Autodesk Fusion 360 part; units mm, degrees
(part 2 of 4)
ref_plane "工作平面9" through (0, -260, 0) normal (0, 1, 0) x (0, 0, 1) in component "07_GPU_REINFORCED_REAR_TOWER"
sketch "草图9 (5)" plane through (0, -260, 0) normal (0, 1, 0) x (1, 0, 0) in component "07_GPU_REINFORCED_REAR_TOWER"
  circle A0 through (81.7, -151, 520) (79.15, -149.5278, 520) (79.15, -152.4722, 520)
extrude "Lower tab receiver height adjustment lower end" cut sketch "草图9 (5)" along normal blind 10 contours A0 in plane through (0, 260, 0) normal (0, 1, 0) bodies 26 in component "07_GPU_REINFORCED_REAR_TOWER"
ref_plane "工作平面10" through (0, -260, 0) normal (0, 1, 0) x (0, 0, 1) in component "07_GPU_REINFORCED_REAR_TOWER"
sketch "草图10 (3)" plane through (0, -260, 0) normal (0, 1, 0) x (1, 0, 0) in component "07_GPU_REINFORCED_REAR_TOWER"
  circle A0 through (81.7, -165, 520) (79.15, -163.5278, 520) (79.15, -166.4722, 520)
extrude "Lower tab receiver height adjustment upper end" cut sketch "草图10 (3)" along normal blind 10 contours A0 in plane through (0, 260, 0) normal (0, 1, 0) bodies 26 in component "07_GPU_REINFORCED_REAR_TOWER"
ref_plane "工作平面11" through (0, -260, 0) normal (0, 1, 0) x (0, 0, 1) in component "07_GPU_REINFORCED_REAR_TOWER"
sketch "草图11 (2)" plane through (0, -260, 0) normal (0, 1, 0) x (1, 0, 0) in component "07_GPU_REINFORCED_REAR_TOWER"
  line L0 (78.3, -151, 520) -> (81.7, -151, 520)
  line L1 (81.7, -151, 520) -> (81.7, -165, 520)
  line L2 (81.7, -165, 520) -> (78.3, -165, 520)
  line L3 (78.3, -165, 520) -> (78.3, -151, 520)
extrude "Lower tab receiver height adjustment web" cut sketch "草图11 (2)" along normal blind 10 contours L0 L1 L2 L3 in plane through (0, 260, 0) normal (0, 1, 0) bodies 26 in component "07_GPU_REINFORCED_REAR_TOWER"
ref_plane "工作平面12" through (0, -260, 0) normal (0, 1, 0) x (0, 0, 1) in component "07_GPU_REINFORCED_REAR_TOWER"
sketch "草图12 (2)" plane through (0, -260, 0) normal (0, 1, 0) x (1, 0, 0) in component "07_GPU_REINFORCED_REAR_TOWER"
  circle A0 through (165.7, -262, 520) (163.15, -260.5278, 520) (163.15, -263.4722, 520)
extrude "Upper carrier height adjustment lower end (1)" cut sketch "草图12 (2)" along normal blind 10 contours A0 in plane through (0, 260, 0) normal (0, 1, 0) bodies 26 in component "07_GPU_REINFORCED_REAR_TOWER"
ref_plane "工作平面13" through (0, -260, 0) normal (0, 1, 0) x (0, 0, 1) in component "07_GPU_REINFORCED_REAR_TOWER"
sketch "草图13 (2)" plane through (0, -260, 0) normal (0, 1, 0) x (1, 0, 0) in component "07_GPU_REINFORCED_REAR_TOWER"
  circle A0 through (165.7, -292, 520) (163.15, -290.5278, 520) (163.15, -293.4722, 520)
extrude "Upper carrier height adjustment upper end (1)" cut sketch "草图13 (2)" along normal blind 10 contours A0 in plane through (0, 260, 0) normal (0, 1, 0) bodies 26 in component "07_GPU_REINFORCED_REAR_TOWER"
ref_plane "工作平面14" through (0, -260, 0) normal (0, 1, 0) x (0, 0, 1) in component "07_GPU_REINFORCED_REAR_TOWER"
sketch "草图14 (2)" plane through (0, -260, 0) normal (0, 1, 0) x (1, 0, 0) in component "07_GPU_REINFORCED_REAR_TOWER"
  line L0 (162.3, -262, 520) -> (165.7, -262, 520)
  line L1 (165.7, -262, 520) -> (165.7, -292, 520)
  line L2 (165.7, -292, 520) -> (162.3, -292, 520)
  line L3 (162.3, -292, 520) -> (162.3, -262, 520)
extrude "Upper carrier height adjustment web (1)" cut sketch "草图14 (2)" along normal blind 10 contours L0 L1 L2 L3 in plane through (0, 260, 0) normal (0, 1, 0) bodies 26 in component "07_GPU_REINFORCED_REAR_TOWER"
ref_plane "工作平面15" through (0, -260, 0) normal (0, 1, 0) x (0, 0, 1) in component "07_GPU_REINFORCED_REAR_TOWER"
sketch "草图15 (2)" plane through (0, -260, 0) normal (0, 1, 0) x (1, 0, 0) in component "07_GPU_REINFORCED_REAR_TOWER"
  circle A0 through (165.7, -151, 520) (163.15, -149.5278, 520) (163.15, -152.4722, 520)
extrude "Lower tab receiver height adjustment lower end (1)" cut sketch "草图15 (2)" along normal blind 10 contours A0 in plane through (0, 260, 0) normal (0, 1, 0) bodies 26 in component "07_GPU_REINFORCED_REAR_TOWER"
ref_plane "工作平面16" through (0, -260, 0) normal (0, 1, 0) x (0, 0, 1) in component "07_GPU_REINFORCED_REAR_TOWER"
sketch "草图16 (2)" plane through (0, -260, 0) normal (0, 1, 0) x (1, 0, 0) in component "07_GPU_REINFORCED_REAR_TOWER"
  circle A0 through (165.7, -165, 520) (163.15, -163.5278, 520) (163.15, -166.4722, 520)
extrude "Lower tab receiver height adjustment upper end (1)" cut sketch "草图16 (2)" along normal blind 10 contours A0 in plane through (0, 260, 0) normal (0, 1, 0) bodies 26 in component "07_GPU_REINFORCED_REAR_TOWER"
ref_plane "工作平面17" through (0, -260, 0) normal (0, 1, 0) x (0, 0, 1) in component "07_GPU_REINFORCED_REAR_TOWER"
sketch "草图17" plane through (0, -260, 0) normal (0, 1, 0) x (1, 0, 0) in component "07_GPU_REINFORCED_REAR_TOWER"
  line L0 (162.3, -151, 520) -> (165.7, -151, 520)
  line L1 (165.7, -151, 520) -> (165.7, -165, 520)
  line L2 (165.7, -165, 520) -> (162.3, -165, 520)
  line L3 (162.3, -165, 520) -> (162.3, -151, 520)
extrude "Lower tab receiver height adjustment web (1)" cut sketch "草图17" along normal blind 10 contours L0 L1 L2 L3 in plane through (0, 260, 0) normal (0, 1, 0) bodies 26 in component "07_GPU_REINFORCED_REAR_TOWER"
ref_plane "工作平面18" through (0, 0, 140) normal (0, 0, 1) x (1, 0, 0) in component "07_GPU_REINFORCED_REAR_TOWER"
sketch "草图18" plane through (0, 0, 140) normal (0, 0, 1) x (1, 0, 0) in component "07_GPU_REINFORCED_REAR_TOWER"
  circle A0 centre (80, 248.5) radius 1.7
extrude "Rear frame mounting screw clearance" cut sketch "草图18" along normal blind 8 bodies 26 in component "07_GPU_REINFORCED_REAR_TOWER"
ref_plane "工作平面19" through (0, 0, 140) normal (0, 0, 1) x (1, 0, 0) in component "07_GPU_REINFORCED_REAR_TOWER"
sketch "草图19" plane through (0, 0, 140) normal (0, 0, 1) x (1, 0, 0) in component "07_GPU_REINFORCED_REAR_TOWER"
  circle A0 centre (140, 248.5) radius 1.7
extrude "Rear frame mounting screw clearance (1)" cut sketch "草图19" along normal blind 8 bodies 26 in component "07_GPU_REINFORCED_REAR_TOWER"
ref_plane "工作平面20" through (0, 0, 140) normal (0, 0, 1) x (1, 0, 0) in component "07_GPU_REINFORCED_REAR_TOWER"
sketch "草图20" plane through (0, 0, 140) normal (0, 0, 1) x (1, 0, 0) in component "07_GPU_REINFORCED_REAR_TOWER"
  circle A0 centre (158, 248.5) radius 1.7
extrude "CPU rear frame screw clearance" cut sketch "草图20" along normal blind 8 bodies 26 in component "07_GPU_REINFORCED_REAR_TOWER"
ref_plane "工作平面1" through (0, 0, 260) normal (0, 0, 1) x (1, 0, 0) in component "08_GPU_UPPER_EAR_LEDGE_ADJUSTABLE"
sketch "草图1 (23)" plane through (0, 0, 260) normal (0, 0, 1) x (1, 0, 0) in component "08_GPU_UPPER_EAR_LEDGE_ADJUSTABLE"
  line L0 (74, 254) -> (170, 254)
  line L1 (170, 254) -> (170, 260)
  line L2 (170, 260) -> (74, 260)
  line L3 (74, 260) -> (74, 254)
extrude "Upper sliding mounting plate" add sketch "草图1 (23)" along normal blind 36 separate body makes body 27 in component "08_GPU_UPPER_EAR_LEDGE_ADJUSTABLE"
ref_plane "工作平面2" through (0, 0, 272) normal (0, 0, 1) x (1, 0, 0) in component "08_GPU_UPPER_EAR_LEDGE_ADJUSTABLE"
sketch "草图2 (14)" plane through (0, 0, 272) normal (0, 0, 1) x (1, 0, 0) in component "08_GPU_UPPER_EAR_LEDGE_ADJUSTABLE"
  line L0 (84, 244.84) -> (154, 244.84)
  line L1 (154, 244.84) -> (154, 254)
  line L2 (154, 254) -> (84, 254)
  line L3 (84, 254) -> (84, 244.84)
extrude "10 mm horizontal ear bearing ledge" add sketch "草图2 (14)" along normal blind 10 bodies 27 in component "08_GPU_UPPER_EAR_LEDGE_ADJUSTABLE"
ref_plane "工作平面3" through (84, 0, 0) normal (1, 0, 0) x (0, 1, 0) in component "08_GPU_UPPER_EAR_LEDGE_ADJUSTABLE"
sketch "草图3 (13)" plane through (84, 0, 0) normal (1, 0, 0) x (0, 0, -1) in component "08_GPU_UPPER_EAR_LEDGE_ADJUSTABLE"
  line L0 (-272, 244.84) -> (-262, 254)
  line L1 (-262, 254) -> (-272, 254)
  line L2 (-272, 254) -> (-272, 244.84)
extrude "Under-ledge triangular gusset" add sketch "草图3 (13)" along normal blind 6 bodies 27 in component "08_GPU_UPPER_EAR_LEDGE_ADJUSTABLE"
ref_plane "工作平面4" through (148, 0, 0) normal (1, 0, 0) x (0, 1, 0) in component "08_GPU_UPPER_EAR_LEDGE_ADJUSTABLE"
sketch "草图4 (11)" plane through (148, 0, 0) normal (1, 0, 0) x (0, 0, -1) in component "08_GPU_UPPER_EAR_LEDGE_ADJUSTABLE"
  line L0 (-272, 244.84) -> (-262, 254)
  line L1 (-262, 254) -> (-272, 254)
  line L2 (-272, 254) -> (-272, 244.84)
extrude "Under-ledge triangular gusset (1)" add sketch "草图4 (11)" along normal blind 6 bodies 27 in component "08_GPU_UPPER_EAR_LEDGE_ADJUSTABLE"
ref_plane "工作平面5" through (0, -254, 0) normal (0, 1, 0) x (0, 0, 1) in component "08_GPU_UPPER_EAR_LEDGE_ADJUSTABLE"
sketch "草图5 (8)" plane through (0, -254, 0) normal (0, 1, 0) x (1, 0, 0) in component "08_GPU_UPPER_EAR_LEDGE_ADJUSTABLE"
  circle A0 through (81.7, -276, 508) (79.15, -274.5278, 508) (79.15, -277.4722, 508)
extrude "M3 carrier clamp through hole" cut sketch "草图5 (8)" along normal blind 6 contours A0 in plane through (0, 254, 0) normal (0, 1, 0) bodies 27 in component "08_GPU_UPPER_EAR_LEDGE_ADJUSTABLE"
ref_plane "工作平面6" through (0, -254, 0) normal (0, 1, 0) x (0, 0, 1) in component "08_GPU_UPPER_EAR_LEDGE_ADJUSTABLE"
sketch "草图6 (8)" plane through (0, -254, 0) normal (0, 1, 0) x (1, 0, 0) in component "08_GPU_UPPER_EAR_LEDGE_ADJUSTABLE"
  circle A0 through (165.7, -276, 508) (163.15, -274.5278, 508) (163.15, -277.4722, 508)
extrude "M3 carrier clamp through hole (1)" cut sketch "草图6 (8)" along normal blind 6 contours A0 in plane through (0, 254, 0) normal (0, 1, 0) bodies 27 in component "08_GPU_UPPER_EAR_LEDGE_ADJUSTABLE"
ref_plane "工作平面7" through (0, 0, 275.5) normal (0, 0, 1) x (1, 0, 0) in component "08_GPU_UPPER_EAR_LEDGE_ADJUSTABLE"
sketch "草图7 (6)" plane through (0, 0, 275.5) normal (0, 0, 1) x (1, 0, 0) in component "08_GPU_UPPER_EAR_LEDGE_ADJUSTABLE"
  circle A0 centre (100, 249.5) radius 2.3
ref_plane "工作平面8" through (0, 0, 275.5) normal (0, 0, 1) x (1, 0, 0) in component "08_GPU_UPPER_EAR_LEDGE_ADJUSTABLE"
sketch "草图8 (6)" plane through (0, 0, 275.5) normal (0, 0, 1) x (1, 0, 0) in component "08_GPU_UPPER_EAR_LEDGE_ADJUSTABLE"
  circle A0 centre (120, 249.5) radius 2.3
ref_plane "工作平面1" through (0, 0, 146) normal (0, 0, 1) x (1, 0, 0) in component "08_GPU_LOWER_TWO_TAB_RECEIVER_ADJUSTABLE"
sketch "草图1 (24)" plane through (0, 0, 146) normal (0, 0, 1) x (1, 0, 0) in component "08_GPU_LOWER_TWO_TAB_RECEIVER_ADJUSTABLE"
  line L0 (74, 254) -> (170, 254)
  line L1 (170, 254) -> (170, 260)
  line L2 (170, 260) -> (74, 260)
  line L3 (74, 260) -> (74, 254)
extrude "Lower sliding receiver back plate" add sketch "草图1 (24)" along normal blind 18 separate body makes body 28 in component "08_GPU_LOWER_TWO_TAB_RECEIVER_ADJUSTABLE"
ref_plane "工作平面2" through (0, 0, 146) normal (0, 0, 1) x (1, 0, 0) in component "08_GPU_LOWER_TWO_TAB_RECEIVER_ADJUSTABLE"
sketch "草图2 (15)" plane through (0, 0, 146) normal (0, 0, 1) x (1, 0, 0) in component "08_GPU_LOWER_TWO_TAB_RECEIVER_ADJUSTABLE"
  line L0 (84, 244.84) -> (140, 244.84)
  line L1 (140, 244.84) -> (140, 254)
  line L2 (140, 254) -> (84, 254)
  line L3 (84, 254) -> (84, 244.84)
extrude "Lower metal tab guide block" add sketch "草图2 (15)" along normal blind 12 bodies 28 in component "08_GPU_LOWER_TWO_TAB_RECEIVER_ADJUSTABLE"
ref_plane "工作平面3" through (0, 0, 145.9) normal (0, 0, 1) x (1, 0, 0) in component "08_GPU_LOWER_TWO_TAB_RECEIVER_ADJUSTABLE"
sketch "草图3 (14)" plane through (0, 0, 145.9) normal (0, 0, 1) x (1, 0, 0) in component "08_GPU_LOWER_TWO_TAB_RECEIVER_ADJUSTABLE"
  line L0 (89, 246.3) -> (103, 246.3)
  line L1 (103, 246.3) -> (103, 248.7)
  line L2 (103, 248.7) -> (89, 248.7)
  line L3 (89, 248.7) -> (89, 246.3)
extrude "Open bottom tab slot - nominal position" cut sketch "草图3 (14)" along normal blind 12.2 bodies 28 in component "08_GPU_LOWER_TWO_TAB_RECEIVER_ADJUSTABLE"
ref_plane "工作平面4" through (0, 0, 145.9) normal (0, 0, 1) x (1, 0, 0) in component "08_GPU_LOWER_TWO_TAB_RECEIVER_ADJUSTABLE"
sketch "草图4 (12)" plane through (0, 0, 145.9) normal (0, 0, 1) x (1, 0, 0) in component "08_GPU_LOWER_TWO_TAB_RECEIVER_ADJUSTABLE"
  line L0 (109, 246.3) -> (123, 246.3)
  line L1 (123, 246.3) -> (123, 248.7)
  line L2 (123, 248.7) -> (109, 248.7)
  line L3 (109, 248.7) -> (109, 246.3)
extrude "Open bottom tab slot - nominal position (1)" cut sketch "草图4 (12)" along normal blind 12.2 bodies 28 in component "08_GPU_LOWER_TWO_TAB_RECEIVER_ADJUSTABLE"
ref_plane "工作平面5" through (0, -254, 0) normal (0, 1, 0) x (0, 0, 1) in component "08_GPU_LOWER_TWO_TAB_RECEIVER_ADJUSTABLE"
sketch "草图5 (9)" plane through (0, -254, 0) normal (0, 1, 0) x (1, 0, 0) in component "08_GPU_LOWER_TWO_TAB_RECEIVER_ADJUSTABLE"
  circle A0 through (81.7, -157, 508) (79.15, -155.5278, 508) (79.15, -158.4722, 508)
extrude "M3 lower receiver clamp through hole" cut sketch "草图5 (9)" along normal blind 6 contours A0 in plane through (0, 254, 0) normal (0, 1, 0) bodies 28 in component "08_GPU_LOWER_TWO_TAB_RECEIVER_ADJUSTABLE"
ref_plane "工作平面6" through (0, -254, 0) normal (0, 1, 0) x (0, 0, 1) in component "08_GPU_LOWER_TWO_TAB_RECEIVER_ADJUSTABLE"
sketch "草图6 (9)" plane through (0, -254, 0) normal (0, 1, 0) x (1, 0, 0) in component "08_GPU_LOWER_TWO_TAB_RECEIVER_ADJUSTABLE"
  circle A0 through (165.7, -157, 508) (163.15, -155.5278, 508) (163.15, -158.4722, 508)
extrude "M3 lower receiver clamp through hole (1)" cut sketch "草图6 (9)" along normal blind 6 contours A0 in plane through (0, 254, 0) normal (0, 1, 0) bodies 28 in component "08_GPU_LOWER_TWO_TAB_RECEIVER_ADJUSTABLE"
ref_plane "工作平面7" through (0, 0, 145.9) normal (0, 0, 1) x (1, 0, 0) in component "08_GPU_LOWER_TWO_TAB_RECEIVER_ADJUSTABLE"
sketch "草图7 (7)" plane through (0, 0, 145.9) normal (0, 0, 1) x (1, 0, 0) in component "08_GPU_LOWER_TWO_TAB_RECEIVER_ADJUSTABLE"
  line L0 (73, 244) -> (171, 244)
  line L1 (171, 244) -> (171, 260.1)
  line L2 (171, 260.1) -> (73, 260.1)
  line L3 (73, 260.1) -> (73, 244)
extrude "Receiver clearance above structural foot" cut sketch "草图7 (7)" along normal blind 2.1 bodies 28 in component "08_GPU_LOWER_TWO_TAB_RECEIVER_ADJUSTABLE"
ref_plane "工作平面21" through (0, 0, 139.9) normal (0, 0, 1) x (1, 0, 0) in component "07_GPU_REINFORCED_REAR_TOWER"
sketch "草图21" plane through (0, 0, 139.9) normal (0, 0, 1) x (1, 0, 0) in component "07_GPU_REINFORCED_REAR_TOWER"
  line L0 (89, 246.3) -> (103, 246.3)
  line L1 (103, 246.3) -> (103, 248.7)
  line L2 (103, 248.7) -> (89, 248.7)
  line L3 (89, 248.7) -> (89, 246.3)
extrude "Through foot clearance below GPU metal tabs" cut sketch "草图21" along normal blind 8.2 bodies 26 in component "07_GPU_REINFORCED_REAR_TOWER"
ref_plane "工作平面22" through (0, 0, 139.9) normal (0, 0, 1) x (1, 0, 0) in component "07_GPU_REINFORCED_REAR_TOWER"
sketch "草图22" plane through (0, 0, 139.9) normal (0, 0, 1) x (1, 0, 0) in component "07_GPU_REINFORCED_REAR_TOWER"
  line L0 (109, 246.3) -> (123, 246.3)
  line L1 (123, 246.3) -> (123, 248.7)
  line L2 (123, 248.7) -> (109, 248.7)
  line L3 (109, 248.7) -> (109, 246.3)
extrude "Through foot clearance below GPU metal tabs (1)" cut sketch "草图22" along normal blind 8.2 bodies 26 in component "07_GPU_REINFORCED_REAR_TOWER"
ref_plane "工作平面5" through (0, 10.1, 0) normal (0, 1, 0) x (0, 0, 1) in component "12_front_PCI_SUPPORT_FRAME"
sketch "草图5 (10)" plane through (0, 10.1, 0) normal (0, 1, 0) x (1, 0, 0) in component "12_front_PCI_SUPPORT_FRAME"
  line L0 (-10, 0, -20.2) -> (12.45, 0, -20.2)
  line L1 (12.45, 0, -20.2) -> (-4, -140, -20.2)
  line L2 (-4, -140, -20.2) -> (-10, -140, -20.2)
  line L3 (-10, -140, -20.2) -> (-10, 0, -20.2)
extrude "Increase PCI inward taper to 16.45 mm" cut sketch "草图5 (10)" along normal blind 16.2 contours L0 L1 L2 L3 in plane through (0, -10.1, 0) normal (0, 1, 0) bodies 24 in component "12_front_PCI_SUPPORT_FRAME"
ref_plane "工作平面5" through (0, 0, 0) normal (0, 0, 1) x (1, 0, 0) in component "12_front_CPU_SUPPORT_FRAME"
sketch "草图5 (11)" plane through (0, 0, 0) normal (0, 0, 1) x (1, 0, 0) in component "12_front_CPU_SUPPORT_FRAME"
  line L0 (298.45, -10) -> (302.45, -10)
  line L1 (302.45, -10) -> (302.45, 6)
  line L2 (302.45, 6) -> (298.45, 6)
  line L3 (298.45, 6) -> (298.45, -10)
extrude "CPU front edge aligned with upper beam" add sketch "草图5 (11)" along normal blind 140 bodies 25 in component "12_front_CPU_SUPPORT_FRAME"
ref_plane "工作平面4" through (0, 0, -0.1) normal (0, 0, 1) x (1, 0, 0) in component "04_front_GROUND_BAR_290mm_FLAT_PSU"
sketch "草图4 (13)" plane through (0, 0, -0.1) normal (0, 0, 1) x (1, 0, 0) in component "04_front_GROUND_BAR_290mm_FLAT_PSU"
  line L0 (24.4, 29.82) -> (28.45, 29.82)
  line L1 (28.45, 29.82) -> (28.45, 50.02)
  line L2 (28.45, 50.02) -> (24.4, 50.02)
  line L3 (24.4, 50.02) -> (24.4, 29.82)
extrude "Floor crossbar shortened for increased PCI taper" cut sketch "草图4 (13)" along normal blind 8.2 bodies 18 in component "04_front_GROUND_BAR_290mm_FLAT_PSU"
ref_plane "工作平面5" through (0, 0, 0) normal (0, 0, 1) x (1, 0, 0) in component "04_front_GROUND_BAR_290mm_FLAT_PSU"
sketch "草图5 (12)" plane through (0, 0, 0) normal (0, 0, 1) x (1, 0, 0) in component "04_front_GROUND_BAR_290mm_FLAT_PSU"
  line L0 (282.45, 29.92) -> (286.45, 29.92)
  line L1 (286.45, 29.92) -> (286.45, 49.92)
  line L2 (286.45, 49.92) -> (282.45, 49.92)
  line L3 (282.45, 49.92) -> (282.45, 29.92)
extrude "Extend floor crossbar to CPU frame" add sketch "草图5 (12)" along normal blind 8 bodies 18 in component "04_front_GROUND_BAR_290mm_FLAT_PSU"
ref_plane "工作平面4" through (0, 0, -0.1) normal (0, 0, 1) x (1, 0, 0) in component "04_rear_GROUND_BAR_290mm_FLAT_PSU"
sketch "草图4 (14)" plane through (0, 0, -0.1) normal (0, 0, 1) x (1, 0, 0) in component "04_rear_GROUND_BAR_290mm_FLAT_PSU"
  line L0 (24.4, 193.82) -> (28.45, 193.82)
  line L1 (28.45, 193.82) -> (28.45, 214.02)
  line L2 (28.45, 214.02) -> (24.4, 214.02)
  line L3 (24.4, 214.02) -> (24.4, 193.82)
extrude "Floor crossbar shortened for increased PCI taper'" cut sketch "草图4 (14)" along normal blind 8.2 bodies 19 in component "04_rear_GROUND_BAR_290mm_FLAT_PSU"
ref_plane "工作平面5" through (0, 0, 0) normal (0, 0, 1) x (1, 0, 0) in component "04_rear_GROUND_BAR_290mm_FLAT_PSU"
sketch "草图5 (13)" plane through (0, 0, 0) normal (0, 0, 1) x (1, 0, 0) in component "04_rear_GROUND_BAR_290mm_FLAT_PSU"
  line L0 (282.45, 193.92) -> (286.45, 193.92)
  line L1 (286.45, 193.92) -> (286.45, 213.92)
  line L2 (286.45, 213.92) -> (282.45, 213.92)
  line L3 (282.45, 213.92) -> (282.45, 193.92)
extrude "Extend floor crossbar to CPU frame'" add sketch "草图5 (13)" along normal blind 8 bodies 19 in component "04_rear_GROUND_BAR_290mm_FLAT_PSU"
ref_plane "工作平面1" through (0, 0, 0) normal (0, 0, 1) x (1, 0, 0) in component "16_CPU_VERTICAL_SIDE_FLUSH_TO_BEAM"
sketch "草图1 (25)" plane through (0, 0, 0) normal (0, 0, 1) x (1, 0, 0) in component "16_CPU_VERTICAL_SIDE_FLUSH_TO_BEAM"
  line L0 (286.45, 6) -> (302.45, 6)
  line L1 (302.45, 6) -> (302.45, 253.84)
  line L2 (302.45, 253.84) -> (286.45, 253.84)
  line L3 (286.45, 253.84) -> (286.45, 6)
extrude "CPU outer face matches beam X302.45" add sketch "草图1 (25)" along normal blind 140 separate body makes body 29 in component "16_CPU_VERTICAL_SIDE_FLUSH_TO_BEAM"
ref_plane "工作平面2" through (0, 0, 16) normal (0, 0, 1) x (1, 0, 0) in component "16_CPU_VERTICAL_SIDE_FLUSH_TO_BEAM"
sketch "草图2 (16)" plane through (0, 0, 16) normal (0, 0, 1) x (1, 0, 0) in component "16_CPU_VERTICAL_SIDE_FLUSH_TO_BEAM"
  line L0 (286.3, 22) -> (302.6, 22)
  line L1 (302.6, 22) -> (302.6, 237.84)
  line L2 (302.6, 237.84) -> (286.3, 237.84)
  line L3 (286.3, 237.84) -> (286.3, 22)
extrude "CPU side open window" cut sketch "草图2 (16)" along normal blind 108 bodies 29 in component "16_CPU_VERTICAL_SIDE_FLUSH_TO_BEAM"
ref_plane "工作平面3" through (286.45, 0, 0) normal (1, 0, 0) x (0, 1, 0) in component "16_CPU_VERTICAL_SIDE_FLUSH_TO_BEAM"
sketch "草图3 (15)" plane through (286.45, 0, 0) normal (1, 0, 0) x (0, 0, -1) in component "16_CPU_VERTICAL_SIDE_FLUSH_TO_BEAM"
  line L0 (-16, 22) -> (-16, 38)
  line L1 (-16, 38) -> (-108, 237.84)
  line L2 (-108, 237.84) -> (-124, 237.84)
  line L3 (-124, 237.84) -> (-16, 22)
extrude "CPU side diagonal" add sketch "草图3 (15)" along normal blind 16 bodies 29 in component "16_CPU_VERTICAL_SIDE_FLUSH_TO_BEAM"
ref_plane "工作平面1" through (0, -6, 0) normal (0, 1, 0) x (0, 0, 1) in component "16_PCI_INSET_SIDE_16_45mm"
sketch "草图1 (26)" plane through (0, -6, 0) normal (0, 1, 0) x (1, 0, 0) in component "16_PCI_INSET_SIDE_16_45mm"
  line L0 (12.45, 0, 12) -> (28.45, 0, 12)
  line L1 (28.45, 0, 12) -> (12, -140, 12)
  line L2 (12, -140, 12) -> (-4, -140, 12)
  line L3 (-4, -140, 12) -> (12.45, 0, 12)
extrude "PCI taper 16.45 over 140 mm height" add sketch "草图1 (26)" along normal blind 247.84 separate body contours L0 L1 L2 L3 in plane through (0, 6, 0) normal (0, 1, 0) makes body 30 in component "16_PCI_INSET_SIDE_16_45mm"
ref_plane "工作平面2" through (0, 0, 16) normal (0, 0, 1) x (1, 0, 0) in component "16_PCI_INSET_SIDE_16_45mm"
sketch "草图2 (17)" plane through (0, 0, 16) normal (0, 0, 1) x (1, 0, 0) in component "16_PCI_INSET_SIDE_16_45mm"
  line L0 (-4.1, 22) -> (28.6, 22)
  line L1 (28.6, 22) -> (28.6, 237.84)
  line L2 (28.6, 237.84) -> (-4.1, 237.84)
  line L3 (-4.1, 237.84) -> (-4.1, 22)
extrude "PCI side open window" cut sketch "草图2 (17)" along normal blind 108 bodies 30 in component "16_PCI_INSET_SIDE_16_45mm"
ref_plane "工作平面3" through (-4, 0, 0) normal (1, 0, 0) x (0, 1, 0) in component "16_PCI_INSET_SIDE_16_45mm"
sketch "草图3 (16)" plane through (-4, 0, 0) normal (1, 0, 0) x (0, 0, -1) in component "16_PCI_INSET_SIDE_16_45mm"
  line L0 (-16, 22) -> (-16, 38)
  line L1 (-16, 38) -> (-108, 237.84)
  line L2 (-108, 237.84) -> (-124, 237.84)
  line L3 (-124, 237.84) -> (-16, 22)
extrude "PCI diagonal before taper trim" add sketch "草图3 (16)" along normal blind 32.45 bodies 30 in component "16_PCI_INSET_SIDE_16_45mm"
ref_plane "工作平面4" through (0, -5.9, 0) normal (0, 1, 0) x (0, 0, 1) in component "16_PCI_INSET_SIDE_16_45mm"
sketch "草图4 (15)" plane through (0, -5.9, 0) normal (0, 1, 0) x (1, 0, 0) in component "16_PCI_INSET_SIDE_16_45mm"
  line L0 (-10, 0, 11.8) -> (12.45, 0, 11.8)
  line L1 (12.45, 0, 11.8) -> (-4, -140, 11.8)
  line L2 (-4, -140, 11.8) -> (-10, -140, 11.8)
  line L3 (-10, -140, 11.8) -> (-10, 0, 11.8)
extrude "Trim diagonal outer tapered face" cut sketch "草图4 (15)" along normal blind 248.1 contours L0 L1 L2 L3 in plane through (0, 5.9, 0) normal (0, 1, 0) bodies 30 in component "16_PCI_INSET_SIDE_16_45mm"
ref_plane "工作平面5" through (0, -5.9, 0) normal (0, 1, 0) x (0, 0, 1) in component "16_PCI_INSET_SIDE_16_45mm"
sketch "草图5 (14)" plane through (0, -5.9, 0) normal (0, 1, 0) x (1, 0, 0) in component "16_PCI_INSET_SIDE_16_45mm"
  line L0 (28.45, 0, 11.8) -> (40, 0, 11.8)
  line L1 (40, 0, 11.8) -> (40, -140, 11.8)
  line L2 (40, -140, 11.8) -> (12, -140, 11.8)
  line L3 (12, -140, 11.8) -> (28.45, 0, 11.8)
extrude "Trim diagonal inner tapered face" cut sketch "草图5 (14)" along normal blind 248.1 contours L0 L1 L2 L3 in plane through (0, 5.9, 0) normal (0, 1, 0) bodies 30 in component "16_PCI_INSET_SIDE_16_45mm"
ref_plane "工作平面6" through (0, -247.34, 0) normal (0, 1, 0) x (0, 0, 1) in component "16_PCI_INSET_SIDE_16_45mm"
sketch "草图6 (10)" plane through (0, -247.34, 0) normal (0, 1, 0) x (1, 0, 0) in component "16_PCI_INSET_SIDE_16_45mm"
  circle A0 through (6.3, -132, 494.68) (2.85, -130.0081, 494.68) (2.85, -133.9919, 494.68)
extrude "Trial short M3 insert in side frame rear end" cut sketch "草图6 (10)" along normal blind 6.5 contours A0 in plane through (0, 247.34, 0) normal (0, 1, 0) bodies 30 in component "16_PCI_INSET_SIDE_16_45mm"
ref_plane "工作平面4" through (0, -247.34, 0) normal (0, 1, 0) x (0, 0, 1) in component "16_CPU_VERTICAL_SIDE_FLUSH_TO_BEAM"
sketch "草图4 (16)" plane through (0, -247.34, 0) normal (0, 1, 0) x (1, 0, 0) in component "16_CPU_VERTICAL_SIDE_FLUSH_TO_BEAM"
  circle A0 through (296.3, -132, 494.68) (292.85, -130.0081, 494.68) (292.85, -133.9919, 494.68)
extrude "Trial short M3 insert in side frame rear end'" cut sketch "草图4 (16)" along normal blind 6.5 contours A0 in plane through (0, 247.34, 0) normal (0, 1, 0) bodies 29 in component "16_CPU_VERTICAL_SIDE_FLUSH_TO_BEAM"
ref_plane "工作平面1" through (0, 0, 140) normal (0, 0, 1) x (1, 0, 0) in component "19_PCI_LONGITUDINAL_BOARD_RAIL_243_84mm"
sketch "草图1 (27)" plane through (0, 0, 140) normal (0, 0, 1) x (1, 0, 0) in component "19_PCI_LONGITUDINAL_BOARD_RAIL_243_84mm"
  line L0 (-4, 0) -> (25.51, 0)
  line L1 (25.51, 0) -> (25.51, 243.84)
  line L2 (25.51, 243.84) -> (-4, 243.84)
  line L3 (-4, 243.84) -> (-4, 0)
extrude "One piece rail fits bed with 5 mm brim" add sketch "草图1 (27)" along normal blind 8 separate body makes body 31 in component "19_PCI_LONGITUDINAL_BOARD_RAIL_243_84mm"
ref_plane "工作平面2" through (0, 0, 148) normal (0, 0, 1) x (1, 0, 0) in component "19_PCI_LONGITUDINAL_BOARD_RAIL_243_84mm"
sketch "草图2 (18)" plane through (0, 0, 148) normal (0, 0, 1) x (1, 0, 0) in component "19_PCI_LONGITUDINAL_BOARD_RAIL_243_84mm"
  circle A0 centre (16.51, 233.68) radius 4
extrude "Board hole 1 unchanged" add sketch "草图2 (18)" along normal blind 10 bodies 31 in component "19_PCI_LONGITUDINAL_BOARD_RAIL_243_84mm"
ref_plane "工作平面3" through (0, 0, 153.1) normal (0, 0, 1) x (1, 0, 0) in component "19_PCI_LONGITUDINAL_BOARD_RAIL_243_84mm"
sketch "草图3 (17)" plane through (0, 0, 153.1) normal (0, 0, 1) x (1, 0, 0) in component "19_PCI_LONGITUDINAL_BOARD_RAIL_243_84mm"
  circle A0 centre (16.51, 233.68) radius 2.35
extrude "Trial M3 H4.5 OD5 board insert 1" cut sketch "草图3 (17)" along normal blind 4.9 bodies 31 in component "19_PCI_LONGITUDINAL_BOARD_RAIL_243_84mm"
ref_plane "工作平面4" through (0, 0, 148) normal (0, 0, 1) x (1, 0, 0) in component "19_PCI_LONGITUDINAL_BOARD_RAIL_243_84mm"
sketch "草图4 (17)" plane through (0, 0, 148) normal (0, 0, 1) x (1, 0, 0) in component "19_PCI_LONGITUDINAL_BOARD_RAIL_243_84mm"
  circle A0 centre (16.51, 78.74) radius 4
extrude "Board hole 4 unchanged" add sketch "草图4 (17)" along normal blind 10 bodies 31 in component "19_PCI_LONGITUDINAL_BOARD_RAIL_243_84mm"
ref_plane "工作平面5" through (0, 0, 153.1) normal (0, 0, 1) x (1, 0, 0) in component "19_PCI_LONGITUDINAL_BOARD_RAIL_243_84mm"
sketch "草图5 (15)" plane through (0, 0, 153.1) normal (0, 0, 1) x (1, 0, 0) in component "19_PCI_LONGITUDINAL_BOARD_RAIL_243_84mm"
  circle A0 centre (16.51, 78.74) radius 2.35
extrude "Trial M3 H4.5 OD5 board insert 4" cut sketch "草图5 (15)" along normal blind 4.9 bodies 31 in component "19_PCI_LONGITUDINAL_BOARD_RAIL_243_84mm"
ref_plane "工作平面6" through (0, 0, 148) normal (0, 0, 1) x (1, 0, 0) in component "19_PCI_LONGITUDINAL_BOARD_RAIL_243_84mm"
sketch "草图6 (11)" plane through (0, 0, 148) normal (0, 0, 1) x (1, 0, 0) in component "19_PCI_LONGITUDINAL_BOARD_RAIL_243_84mm"
  circle A0 centre (16.51, 6.35) radius 4
extrude "Board hole 7 unchanged" add sketch "草图6 (11)" along normal blind 10 bodies 31 in component "19_PCI_LONGITUDINAL_BOARD_RAIL_243_84mm"
ref_plane "工作平面7" through (0, 0, 153.1) normal (0, 0, 1) x (1, 0, 0) in component "19_PCI_LONGITUDINAL_BOARD_RAIL_243_84mm"
sketch "草图7 (8)" plane through (0, 0, 153.1) normal (0, 0, 1) x (1, 0, 0) in component "19_PCI_LONGITUDINAL_BOARD_RAIL_243_84mm"
  circle A0 centre (16.51, 6.35) radius 2.35
extrude "Trial M3 H4.5 OD5 board insert 7" cut sketch "草图7 (8)" along normal blind 4.9 bodies 31 in component "19_PCI_LONGITUDINAL_BOARD_RAIL_243_84mm"
ref_plane "工作平面8" through (0, 0, 140) normal (0, 0, 1) x (1, 0, 0) in component "19_PCI_LONGITUDINAL_BOARD_RAIL_243_84mm"
sketch "草图8 (7)" plane through (0, 0, 140) normal (0, 0, 1) x (1, 0, 0) in component "19_PCI_LONGITUDINAL_BOARD_RAIL_243_84mm"
  circle A0 centre (4, 20) radius 1.7
extrude "M3 side rail mounting clearance" cut sketch "草图8 (7)" along normal blind 8 bodies 31 in component "19_PCI_LONGITUDINAL_BOARD_RAIL_243_84mm"
ref_plane "工作平面7" through (0, 0, 133.5) normal (0, 0, 1) x (1, 0, 0) in component "16_PCI_INSET_SIDE_16_45mm"
sketch "草图7 (9)" plane through (0, 0, 133.5) normal (0, 0, 1) x (1, 0, 0) in component "16_PCI_INSET_SIDE_16_45mm"
  circle A0 centre (4, 20) radius 2.35
extrude "Trial short insert for side rail anchor" cut sketch "草图7 (9)" along normal blind 6.5 bodies 30 in component "16_PCI_INSET_SIDE_16_45mm"
ref_plane "工作平面9" through (0, 0, 140) normal (0, 0, 1) x (1, 0, 0) in component "19_PCI_LONGITUDINAL_BOARD_RAIL_243_84mm"
sketch "草图9 (6)" plane through (0, 0, 140) normal (0, 0, 1) x (1, 0, 0) in component "19_PCI_LONGITUDINAL_BOARD_RAIL_243_84mm"
  circle A0 centre (4, 225) radius 1.7
extrude "M3 side rail mounting clearance (1)" cut sketch "草图9 (6)" along normal blind 8 bodies 31 in component "19_PCI_LONGITUDINAL_BOARD_RAIL_243_84mm"
ref_plane "工作平面8" through (0, 0, 133.5) normal (0, 0, 1) x (1, 0, 0) in component "16_PCI_INSET_SIDE_16_45mm"
sketch "草图8 (8)" plane through (0, 0, 133.5) normal (0, 0, 1) x (1, 0, 0) in component "16_PCI_INSET_SIDE_16_45mm"
  circle A0 centre (4, 225) radius 2.35
extrude "Trial short insert for side rail anchor (1)" cut sketch "草图8 (8)" along normal blind 6.5 bodies 30 in component "16_PCI_INSET_SIDE_16_45mm"
ref_plane "工作平面1" through (0, 0, 140) normal (0, 0, 1) x (1, 0, 0) in component "19_MID_LONGITUDINAL_BOARD_RAIL_243_84mm"
sketch "草图1 (28)" plane through (0, 0, 140) normal (0, 0, 1) x (1, 0, 0) in component "19_MID_LONGITUDINAL_BOARD_RAIL_243_84mm"
  line L0 (131.97, 0) -> (149.97, 0)
  line L1 (149.97, 0) -> (149.97, 243.84)
  line L2 (149.97, 243.84) -> (131.97, 243.84)
  line L3 (131.97, 243.84) -> (131.97, 0)
extrude "One piece rail fits bed with 5 mm brim'" add sketch "草图1 (28)" along normal blind 8 separate body makes body 32 in component "19_MID_LONGITUDINAL_BOARD_RAIL_243_84mm"
ref_plane "工作平面2" through (0, 0, 128) normal (0, 0, 1) x (1, 0, 0) in component "19_MID_LONGITUDINAL_BOARD_RAIL_243_84mm"
sketch "草图2 (19)" plane through (0, 0, 128) normal (0, 0, 1) x (1, 0, 0) in component "19_MID_LONGITUDINAL_BOARD_RAIL_243_84mm"
  line L0 (136.97, 6) -> (144.97, 6)
  line L1 (144.97, 6) -> (144.97, 218.5)
  line L2 (144.97, 218.5) -> (136.97, 218.5)
  line L3 (136.97, 218.5) -> (136.97, 6)
extrude "Middle rail underside rib" add sketch "草图2 (19)" along normal blind 12 bodies 32 in component "19_MID_LONGITUDINAL_BOARD_RAIL_243_84mm"
ref_plane "工作平面3" through (0, -6, 0) normal (0, 1, 0) x (0, 0, 1) in component "19_MID_LONGITUDINAL_BOARD_RAIL_243_84mm"
sketch "草图3 (18)" plane through (0, -6, 0) normal (0, 1, 0) x (1, 0, 0) in component "19_MID_LONGITUDINAL_BOARD_RAIL_243_84mm"
  line L0 (136.97, -134, 12) -> (144.97, -134, 12)
  line L1 (144.97, -134, 12) -> (149.97, -140, 12)
  line L2 (149.97, -140, 12) -> (131.97, -140, 12)
  line L3 (131.97, -140, 12) -> (136.97, -134, 12)
extrude "45 degree printable rib transition" add sketch "草图3 (18)" along normal blind 212.5 contours L0 L1 L2 L3 in plane through (0, 6, 0) normal (0, 1, 0) bodies 32 in component "19_MID_LONGITUDINAL_BOARD_RAIL_243_84mm"
ref_plane "工作平面4" through (0, 0, 148) normal (0, 0, 1) x (1, 0, 0) in component "19_MID_LONGITUDINAL_BOARD_RAIL_243_84mm"
sketch "草图4 (18)" plane through (0, 0, 148) normal (0, 0, 1) x (1, 0, 0) in component "19_MID_LONGITUDINAL_BOARD_RAIL_243_84mm"
  circle A0 centre (140.97, 233.68) radius 4
extrude "Board hole 2 unchanged" add sketch "草图4 (18)" along normal blind 10 bodies 32 in component "19_MID_LONGITUDINAL_BOARD_RAIL_243_84mm"
ref_plane "工作平面5" through (0, 0, 153.1) normal (0, 0, 1) x (1, 0, 0) in component "19_MID_LONGITUDINAL_BOARD_RAIL_243_84mm"
sketch "草图5 (16)" plane through (0, 0, 153.1) normal (0, 0, 1) x (1, 0, 0) in component "19_MID_LONGITUDINAL_BOARD_RAIL_243_84mm"
  circle A0 centre (140.97, 233.68) radius 2.35
extrude "Trial M3 H4.5 OD5 board insert 2" cut sketch "草图5 (16)" along normal blind 4.9 bodies 32 in component "19_MID_LONGITUDINAL_BOARD_RAIL_243_84mm"
ref_plane "工作平面6" through (0, 0, 148) normal (0, 0, 1) x (1, 0, 0) in component "19_MID_LONGITUDINAL_BOARD_RAIL_243_84mm"
sketch "草图6 (12)" plane through (0, 0, 148) normal (0, 0, 1) x (1, 0, 0) in component "19_MID_LONGITUDINAL_BOARD_RAIL_243_84mm"
  circle A0 centre (140.97, 78.74) radius 4
extrude "Board hole 5 unchanged" add sketch "草图6 (12)" along normal blind 10 bodies 32 in component "19_MID_LONGITUDINAL_BOARD_RAIL_243_84mm"
ref_plane "工作平面7" through (0, 0, 153.1) normal (0, 0, 1) x (1, 0, 0) in component "19_MID_LONGITUDINAL_BOARD_RAIL_243_84mm"
sketch "草图7 (10)" plane through (0, 0, 153.1) normal (0, 0, 1) x (1, 0, 0) in component "19_MID_LONGITUDINAL_BOARD_RAIL_243_84mm"
  circle A0 centre (140.97, 78.74) radius 2.35
extrude "Trial M3 H4.5 OD5 board insert 5" cut sketch "草图7 (10)" along normal blind 4.9 bodies 32 in component "19_MID_LONGITUDINAL_BOARD_RAIL_243_84mm"
ref_plane "工作平面8" through (0, 0, 148) normal (0, 0, 1) x (1, 0, 0) in component "19_MID_LONGITUDINAL_BOARD_RAIL_243_84mm"
sketch "草图8 (9)" plane through (0, 0, 148) normal (0, 0, 1) x (1, 0, 0) in component "19_MID_LONGITUDINAL_BOARD_RAIL_243_84mm"
  circle A0 centre (140.97, 6.35) radius 4
extrude "Board hole 8 unchanged" add sketch "草图8 (9)" along normal blind 10 bodies 32 in component "19_MID_LONGITUDINAL_BOARD_RAIL_243_84mm"
ref_plane "工作平面9" through (0, 0, 153.1) normal (0, 0, 1) x (1, 0, 0) in component "19_MID_LONGITUDINAL_BOARD_RAIL_243_84mm"
sketch "草图9 (7)" plane through (0, 0, 153.1) normal (0, 0, 1) x (1, 0, 0) in component "19_MID_LONGITUDINAL_BOARD_RAIL_243_84mm"
  circle A0 centre (140.97, 6.35) radius 2.35
extrude "Trial M3 H4.5 OD5 board insert 8" cut sketch "草图9 (7)" along normal blind 4.9 bodies 32 in component "19_MID_LONGITUDINAL_BOARD_RAIL_243_84mm"
ref_plane "工作平面10" through (0, 0, 140) normal (0, 0, 1) x (1, 0, 0) in component "19_MID_LONGITUDINAL_BOARD_RAIL_243_84mm"
sketch "草图10 (4)" plane through (0, 0, 140) normal (0, 0, 1) x (1, 0, 0) in component "19_MID_LONGITUDINAL_BOARD_RAIL_243_84mm"
  circle A0 centre (134, 3) radius 1.7
extrude "Centre rail front mounting clearance" cut sketch "草图10 (4)" along normal blind 8 bodies 32 in component "19_MID_LONGITUDINAL_BOARD_RAIL_243_84mm"
ref_plane "工作平面6" through (0, 0, 133.5) normal (0, 0, 1) x (1, 0, 0) in component "12_front_PCI_SUPPORT_FRAME"
sketch "草图6 (13)" plane through (0, 0, 133.5) normal (0, 0, 1) x (1, 0, 0) in component "12_front_PCI_SUPPORT_FRAME"
  circle A0 centre (134, 3) radius 2.35
extrude "Trial short insert for middle rail front anchor" cut sketch "草图6 (13)" along normal blind 6.5 bodies 24 in component "12_front_PCI_SUPPORT_FRAME"
ref_plane "工作平面11" through (0, 0, 140) normal (0, 0, 1) x (1, 0, 0) in component "19_MID_LONGITUDINAL_BOARD_RAIL_243_84mm"
sketch "草图11 (3)" plane through (0, 0, 140) normal (0, 0, 1) x (1, 0, 0) in component "19_MID_LONGITUDINAL_BOARD_RAIL_243_84mm"
  circle A0 centre (140.97, 222.5) radius 1.7
ref_plane "工作平面1" through (0, 0, 140) normal (0, 0, 1) x (1, 0, 0) in component "19_CPU_LONGITUDINAL_BOARD_RAIL_243_84mm"
sketch "草图1 (29)" plane through (0, 0, 140) normal (0, 0, 1) x (1, 0, 0) in component "19_CPU_LONGITUDINAL_BOARD_RAIL_243_84mm"
  line L0 (286.45, 0) -> (302.45, 0)
  line L1 (302.45, 0) -> (302.45, 243.84)
  line L2 (302.45, 243.84) -> (286.45, 243.84)
  line L3 (286.45, 243.84) -> (286.45, 0)
extrude "One piece rail fits bed with 5 mm brim''" add sketch "草图1 (29)" along normal blind 8 separate body makes body 33 in component "19_CPU_LONGITUDINAL_BOARD_RAIL_243_84mm"
ref_plane "工作平面2" through (0, 0, 148) normal (0, 0, 1) x (1, 0, 0) in component "19_CPU_LONGITUDINAL_BOARD_RAIL_243_84mm"
sketch "草图2 (20)" plane through (0, 0, 148) normal (0, 0, 1) x (1, 0, 0) in component "19_CPU_LONGITUDINAL_BOARD_RAIL_243_84mm"
  circle A0 centre (298.45, 210.82) radius 4
extrude "Board hole 3 unchanged" add sketch "草图2 (20)" along normal blind 10 bodies 33 in component "19_CPU_LONGITUDINAL_BOARD_RAIL_243_84mm"
ref_plane "工作平面3" through (0, 0, 153.1) normal (0, 0, 1) x (1, 0, 0) in component "19_CPU_LONGITUDINAL_BOARD_RAIL_243_84mm"
sketch "草图3 (19)" plane through (0, 0, 153.1) normal (0, 0, 1) x (1, 0, 0) in component "19_CPU_LONGITUDINAL_BOARD_RAIL_243_84mm"
  circle A0 centre (298.45, 210.82) radius 2.35
extrude "Trial M3 H4.5 OD5 board insert 3" cut sketch "草图3 (19)" along normal blind 4.9 bodies 33 in component "19_CPU_LONGITUDINAL_BOARD_RAIL_243_84mm"
ref_plane "工作平面4" through (0, 0, 148) normal (0, 0, 1) x (1, 0, 0) in component "19_CPU_LONGITUDINAL_BOARD_RAIL_243_84mm"
sketch "草图4 (19)" plane through (0, 0, 148) normal (0, 0, 1) x (1, 0, 0) in component "19_CPU_LONGITUDINAL_BOARD_RAIL_243_84mm"
  circle A0 centre (298.45, 78.74) radius 4
extrude "Board hole 6 unchanged" add sketch "草图4 (19)" along normal blind 10 bodies 33 in component "19_CPU_LONGITUDINAL_BOARD_RAIL_243_84mm"
ref_plane "工作平面5" through (0, 0, 153.1) normal (0, 0, 1) x (1, 0, 0) in component "19_CPU_LONGITUDINAL_BOARD_RAIL_243_84mm"
sketch "草图5 (17)" plane through (0, 0, 153.1) normal (0, 0, 1) x (1, 0, 0) in component "19_CPU_LONGITUDINAL_BOARD_RAIL_243_84mm"
  circle A0 centre (298.45, 78.74) radius 2.35
extrude "Trial M3 H4.5 OD5 board insert 6" cut sketch "草图5 (17)" along normal blind 4.9 bodies 33 in component "19_CPU_LONGITUDINAL_BOARD_RAIL_243_84mm"
ref_plane "工作平面6" through (0, 0, 148) normal (0, 0, 1) x (1, 0, 0) in component "19_CPU_LONGITUDINAL_BOARD_RAIL_243_84mm"
sketch "草图6 (14)" plane through (0, 0, 148) normal (0, 0, 1) x (1, 0, 0) in component "19_CPU_LONGITUDINAL_BOARD_RAIL_243_84mm"
  circle A0 centre (298.45, 6.35) radius 4
extrude "Board hole 9 unchanged" add sketch "草图6 (14)" along normal blind 10 bodies 33 in component "19_CPU_LONGITUDINAL_BOARD_RAIL_243_84mm"
ref_plane "工作平面7" through (0, 0, 153.1) normal (0, 0, 1) x (1, 0, 0) in component "19_CPU_LONGITUDINAL_BOARD_RAIL_243_84mm"
sketch "草图7 (11)" plane through (0, 0, 153.1) normal (0, 0, 1) x (1, 0, 0) in component "19_CPU_LONGITUDINAL_BOARD_RAIL_243_84mm"
  circle A0 centre (298.45, 6.35) radius 2.35
extrude "Trial M3 H4.5 OD5 board insert 9" cut sketch "草图7 (11)" along normal blind 4.9 bodies 33 in component "19_CPU_LONGITUDINAL_BOARD_RAIL_243_84mm"
ref_plane "工作平面8" through (0, 0, 140) normal (0, 0, 1) x (1, 0, 0) in component "19_CPU_LONGITUDINAL_BOARD_RAIL_243_84mm"
sketch "草图8 (10)" plane through (0, 0, 140) normal (0, 0, 1) x (1, 0, 0) in component "19_CPU_LONGITUDINAL_BOARD_RAIL_243_84mm"
  circle A0 centre (294, 20) radius 1.7
extrude "M3 side rail mounting clearance'" cut sketch "草图8 (10)" along normal blind 8 bodies 33 in component "19_CPU_LONGITUDINAL_BOARD_RAIL_243_84mm"
ref_plane "工作平面5" through (0, 0, 133.5) normal (0, 0, 1) x (1, 0, 0) in component "16_CPU_VERTICAL_SIDE_FLUSH_TO_BEAM"
sketch "草图5 (18)" plane through (0, 0, 133.5) normal (0, 0, 1) x (1, 0, 0) in component "16_CPU_VERTICAL_SIDE_FLUSH_TO_BEAM"
  circle A0 centre (294, 20) radius 2.35
extrude "Trial short insert for side rail anchor'" cut sketch "草图5 (18)" along normal blind 6.5 bodies 29 in component "16_CPU_VERTICAL_SIDE_FLUSH_TO_BEAM"
ref_plane "工作平面9" through (0, 0, 140) normal (0, 0, 1) x (1, 0, 0) in component "19_CPU_LONGITUDINAL_BOARD_RAIL_243_84mm"
sketch "草图9 (8)" plane through (0, 0, 140) normal (0, 0, 1) x (1, 0, 0) in component "19_CPU_LONGITUDINAL_BOARD_RAIL_243_84mm"
  circle A0 centre (294, 225) radius 1.7
extrude "M3 side rail mounting clearance (1)'" cut sketch "草图9 (8)" along normal blind 8 bodies 33 in component "19_CPU_LONGITUDINAL_BOARD_RAIL_243_84mm"
ref_plane "工作平面6" through (0, 0, 133.5) normal (0, 0, 1) x (1, 0, 0) in component "16_CPU_VERTICAL_SIDE_FLUSH_TO_BEAM"
sketch "草图6 (15)" plane through (0, 0, 133.5) normal (0, 0, 1) x (1, 0, 0) in component "16_CPU_VERTICAL_SIDE_FLUSH_TO_BEAM"
  circle A0 centre (294, 225) radius 2.35
extrude "Trial short insert for side rail anchor (1)'" cut sketch "草图6 (15)" along normal blind 6.5 bodies 29 in component "16_CPU_VERTICAL_SIDE_FLUSH_TO_BEAM"
ref_plane "工作平面7" through (0, 0, 133.5) normal (0, 0, 1) x (1, 0, 0) in component "12_front_PCI_SUPPORT_FRAME"
sketch "草图7 (12)" plane through (0, 0, 133.5) normal (0, 0, 1) x (1, 0, 0) in component "12_front_PCI_SUPPORT_FRAME"
  circle A0 centre (50, 2) radius 2.35
extrude "Trial short insert for fan shoe anchor" cut sketch "草图7 (12)" along normal blind 6.5 bodies 24 in component "12_front_PCI_SUPPORT_FRAME"
ref_plane "工作平面8" through (0, 0, 133.5) normal (0, 0, 1) x (1, 0, 0) in component "12_front_PCI_SUPPORT_FRAME"
sketch "草图8 (11)" plane through (0, 0, 133.5) normal (0, 0, 1) x (1, 0, 0) in component "12_front_PCI_SUPPORT_FRAME"
  circle A0 centre (110, 2) radius 2.35
extrude "Trial short insert for fan shoe anchor (1)" cut sketch "草图8 (11)" along normal blind 6.5 bodies 24 in component "12_front_PCI_SUPPORT_FRAME"
ref_plane "工作平面6" through (0, 0, 133.5) normal (0, 0, 1) x (1, 0, 0) in component "12_front_CPU_SUPPORT_FRAME"
sketch "草图6 (16)" plane through (0, 0, 133.5) normal (0, 0, 1) x (1, 0, 0) in component "12_front_CPU_SUPPORT_FRAME"
  circle A0 centre (200, 2) radius 2.35
extrude "Trial short insert for fan shoe anchor'" cut sketch "草图6 (16)" along normal blind 6.5 bodies 25 in component "12_front_CPU_SUPPORT_FRAME"
ref_plane "工作平面7" through (0, 0, 133.5) normal (0, 0, 1) x (1, 0, 0) in component "12_front_CPU_SUPPORT_FRAME"
sketch "草图7 (13)" plane through (0, 0, 133.5) normal (0, 0, 1) x (1, 0, 0) in component "12_front_CPU_SUPPORT_FRAME"
  circle A0 centre (265, 2) radius 2.35
extrude "Trial short insert for fan shoe anchor (1)'" cut sketch "草图7 (13)" along normal blind 6.5 bodies 25 in component "12_front_CPU_SUPPORT_FRAME"
ref_plane "工作平面12" through (0, 0, 128) normal (0, 0, 1) x (1, 0, 0) in component "19_MID_LONGITUDINAL_BOARD_RAIL_243_84mm"
sketch "草图12 (3)" plane through (0, 0, 128) normal (0, 0, 1) x (1, 0, 0) in component "19_MID_LONGITUDINAL_BOARD_RAIL_243_84mm"
  line L0 (136.97, 218.5) -> (144.97, 218.5)
  line L1 (144.97, 218.5) -> (144.97, 237.84)
  line L2 (144.97, 237.84) -> (136.97, 237.84)
  line L3 (136.97, 237.84) -> (136.97, 218.5)
extrude "Continue underside rib nearly to rail end" add sketch "草图12 (3)" along normal blind 12 bodies 32 in component "19_MID_LONGITUDINAL_BOARD_RAIL_243_84mm"
ref_plane "工作平面13" through (0, -218.5, 0) normal (0, 1, 0) x (0, 0, 1) in component "19_MID_LONGITUDINAL_BOARD_RAIL_243_84mm"
sketch "草图13 (3)" plane through (0, -218.5, 0) normal (0, 1, 0) x (1, 0, 0) in component "19_MID_LONGITUDINAL_BOARD_RAIL_243_84mm"
  line L0 (136.97, -134, 437) -> (144.97, -134, 437)
  line L1 (144.97, -134, 437) -> (149.97, -140, 437)
  line L2 (149.97, -140, 437) -> (131.97, -140, 437)
  line L3 (131.97, -140, 437) -> (136.97, -134, 437)
ref_plane "工作平面14" through (0, 0, 140) normal (0, 0, 1) x (1, 0, 0) in component "19_MID_LONGITUDINAL_BOARD_RAIL_243_84mm"
sketch "草图14 (3)" plane through (0, 0, 140) normal (0, 0, 1) x (1, 0, 0) in component "19_MID_LONGITUDINAL_BOARD_RAIL_243_84mm"
  circle A0 centre (134, 222.5) radius 1.7
extrude "Centre rail rear seat mounting clearance" cut sketch "草图14 (3)" along normal blind 8 bodies 32 in component "19_MID_LONGITUDINAL_BOARD_RAIL_243_84mm"
ref_plane "工作平面1" through (0, -242.68, 0) normal (0, 1, 0) x (0, 0, 1) in component "18_ONE_PIECE_REAR_LOAD_BEAM_304_45mm"
sketch "草图1 (30)" plane through (0, -242.68, 0) normal (0, 1, 0) x (1, 0, 0) in component "18_ONE_PIECE_REAR_LOAD_BEAM_304_45mm"
  line L0 (13.41, -128, 485.36) -> (286.45, -128, 485.36)
  line L1 (286.45, -128, 485.36) -> (286.45, -140, 485.36)
  line L2 (286.45, -140, 485.36) -> (12, -140, 485.36)
  line L3 (12, -140, 485.36) -> (13.41, -128, 485.36)
extrude "Continuous full depth rear beam without centre joint" add sketch "草图1 (30)" along normal blind 23.16 separate body contours L0 L1 L2 L3 in plane through (0, 242.68, 0) normal (0, 1, 0) makes body 34 in component "18_ONE_PIECE_REAR_LOAD_BEAM_304_45mm"
ref_plane "工作平面2" through (0, -242.68, 0) normal (0, 1, 0) x (0, 0, 1) in component "18_ONE_PIECE_REAR_LOAD_BEAM_304_45mm"
sketch "草图2 (21)" plane through (0, -242.68, 0) normal (0, 1, 0) x (1, 0, 0) in component "18_ONE_PIECE_REAR_LOAD_BEAM_304_45mm"
  line L0 (102.4, -128, 485.36) -> (122.4, -120, 485.36)
  line L1 (122.4, -120, 485.36) -> (182.4, -120, 485.36)
  line L2 (182.4, -120, 485.36) -> (202.4, -128, 485.36)
  line L3 (202.4, -128, 485.36) -> (102.4, -128, 485.36)
extrude "Continuous central load spreading rib" add sketch "草图2 (21)" along normal blind 23.16 contours L0 L1 L2 L3 in plane through (0, 242.68, 0) normal (0, 1, 0) bodies 34 in component "18_ONE_PIECE_REAR_LOAD_BEAM_304_45mm"
ref_plane "工作平面3" through (0, 0, 124) normal (0, 0, 1) x (1, 0, 0) in component "18_ONE_PIECE_REAR_LOAD_BEAM_304_45mm"
sketch "草图3 (20)" plane through (0, 0, 124) normal (0, 0, 1) x (1, 0, 0) in component "18_ONE_PIECE_REAR_LOAD_BEAM_304_45mm"
  line L0 (-2, 253.84) -> (26, 253.84)
  line L1 (26, 253.84) -> (26, 261.84)
  line L2 (26, 261.84) -> (-2, 261.84)
  line L3 (-2, 261.84) -> (-2, 253.84)
extrude "Integral PCI end fastening ear" add sketch "草图3 (20)" along normal blind 16 bodies 34 in component "18_ONE_PIECE_REAR_LOAD_BEAM_304_45mm"
ref_plane "工作平面4" through (0, 0, 124) normal (0, 0, 1) x (1, 0, 0) in component "18_ONE_PIECE_REAR_LOAD_BEAM_304_45mm"
sketch "草图4 (20)" plane through (0, 0, 124) normal (0, 0, 1) x (1, 0, 0) in component "18_ONE_PIECE_REAR_LOAD_BEAM_304_45mm"
  line L0 (270, 253.84) -> (302.45, 253.84)
  line L1 (302.45, 253.84) -> (302.45, 261.84)
  line L2 (302.45, 261.84) -> (270, 261.84)
  line L3 (270, 261.84) -> (270, 253.84)
extrude "Integral CPU end fastening ear" add sketch "草图4 (20)" along normal blind 16 bodies 34 in component "18_ONE_PIECE_REAR_LOAD_BEAM_304_45mm"
ref_plane "工作平面5" through (0, 0, 128) normal (0, 0, 1) x (1, 0, 0) in component "18_ONE_PIECE_REAR_LOAD_BEAM_304_45mm"
sketch "草图5 (19)" plane through (0, 0, 128) normal (0, 0, 1) x (1, 0, 0) in component "18_ONE_PIECE_REAR_LOAD_BEAM_304_45mm"
  line L0 (130, 218.5) -> (152.4, 218.5)
  line L1 (152.4, 218.5) -> (152.4, 242.68)
  line L2 (152.4, 242.68) -> (130, 242.68)
  line L3 (130, 242.68) -> (130, 218.5)
extrude "Integral seat for middle motherboard rail" add sketch "草图5 (19)" along normal blind 12 bodies 34 in component "18_ONE_PIECE_REAR_LOAD_BEAM_304_45mm"
ref_plane "工作平面6" through (0, 0, 127.9) normal (0, 0, 1) x (1, 0, 0) in component "18_ONE_PIECE_REAR_LOAD_BEAM_304_45mm"
sketch "草图6 (17)" plane through (0, 0, 127.9) normal (0, 0, 1) x (1, 0, 0) in component "18_ONE_PIECE_REAR_LOAD_BEAM_304_45mm"
  line L0 (136.77, 218.5) -> (145.17, 218.5)
  line L1 (145.17, 218.5) -> (145.17, 237.84)
  line L2 (145.17, 237.84) -> (136.77, 237.84)
  line L3 (136.77, 237.84) -> (136.77, 218.5)
extrude "Middle rail rib clearance with 0.2 mm each side" cut sketch "草图6 (17)" along normal blind 12.2 bodies 34 in component "18_ONE_PIECE_REAR_LOAD_BEAM_304_45mm"
ref_plane "工作平面7" through (0, 0, 133.5) normal (0, 0, 1) x (1, 0, 0) in component "18_ONE_PIECE_REAR_LOAD_BEAM_304_45mm"
sketch "草图7 (14)" plane through (0, 0, 133.5) normal (0, 0, 1) x (1, 0, 0) in component "18_ONE_PIECE_REAR_LOAD_BEAM_304_45mm"
  circle A0 centre (134, 222.5) radius 2.35
extrude "M3 H4.5 insert for middle rail" cut sketch "草图7 (14)" along normal blind 6.5 bodies 34 in component "18_ONE_PIECE_REAR_LOAD_BEAM_304_45mm"
ref_plane "工作平面8" through (0, 0, 133.5) normal (0, 0, 1) x (1, 0, 0) in component "18_ONE_PIECE_REAR_LOAD_BEAM_304_45mm"
sketch "草图8 (12)" plane through (0, 0, 133.5) normal (0, 0, 1) x (1, 0, 0) in component "18_ONE_PIECE_REAR_LOAD_BEAM_304_45mm"
  circle A0 centre (80, 248.5) radius 2.35
extrude "M3 H4.5 insert for GPU tower" cut sketch "草图8 (12)" along normal blind 6.5 bodies 34 in component "18_ONE_PIECE_REAR_LOAD_BEAM_304_45mm"
ref_plane "工作平面9" through (0, 0, 133.5) normal (0, 0, 1) x (1, 0, 0) in component "18_ONE_PIECE_REAR_LOAD_BEAM_304_45mm"
sketch "草图9 (9)" plane through (0, 0, 133.5) normal (0, 0, 1) x (1, 0, 0) in component "18_ONE_PIECE_REAR_LOAD_BEAM_304_45mm"
  circle A0 centre (140, 248.5) radius 2.35
extrude "M3 H4.5 insert for GPU tower (1)" cut sketch "草图9 (9)" along normal blind 6.5 bodies 34 in component "18_ONE_PIECE_REAR_LOAD_BEAM_304_45mm"
ref_plane "工作平面10" through (0, 0, 133.5) normal (0, 0, 1) x (1, 0, 0) in component "18_ONE_PIECE_REAR_LOAD_BEAM_304_45mm"
sketch "草图10 (5)" plane through (0, 0, 133.5) normal (0, 0, 1) x (1, 0, 0) in component "18_ONE_PIECE_REAR_LOAD_BEAM_304_45mm"
  circle A0 centre (158, 248.5) radius 2.35
extrude "M3 H4.5 insert for GPU tower (2)" cut sketch "草图10 (5)" along normal blind 6.5 bodies 34 in component "18_ONE_PIECE_REAR_LOAD_BEAM_304_45mm"
ref_plane "工作平面11" through (0, 0, 119.9) normal (0, 0, 1) x (1, 0, 0) in component "18_ONE_PIECE_REAR_LOAD_BEAM_304_45mm"
sketch "草图11 (4)" plane through (0, 0, 119.9) normal (0, 0, 1) x (1, 0, 0) in component "18_ONE_PIECE_REAR_LOAD_BEAM_304_45mm"
  line L0 (89, 246.3) -> (103, 246.3)
  line L1 (103, 246.3) -> (103, 248.7)
  line L2 (103, 248.7) -> (89, 248.7)
  line L3 (89, 248.7) -> (89, 246.3)
extrude "GPU lower metal tab exit" cut sketch "草图11 (4)" along normal blind 20.2 bodies 34 in component "18_ONE_PIECE_REAR_LOAD_BEAM_304_45mm"
ref_plane "工作平面12" through (0, 0, 119.9) normal (0, 0, 1) x (1, 0, 0) in component "18_ONE_PIECE_REAR_LOAD_BEAM_304_45mm"
sketch "草图12 (4)" plane through (0, 0, 119.9) normal (0, 0, 1) x (1, 0, 0) in component "18_ONE_PIECE_REAR_LOAD_BEAM_304_45mm"
  line L0 (109, 246.3) -> (123, 246.3)
  line L1 (123, 246.3) -> (123, 248.7)
  line L2 (123, 248.7) -> (109, 248.7)
  line L3 (109, 248.7) -> (109, 246.3)
extrude "GPU lower metal tab exit (1)" cut sketch "草图12 (4)" along normal blind 20.2 bodies 34 in component "18_ONE_PIECE_REAR_LOAD_BEAM_304_45mm"
ref_plane "工作平面13" through (0, -253.84, 0) normal (0, 1, 0) x (0, 0, 1) in component "18_ONE_PIECE_REAR_LOAD_BEAM_304_45mm"